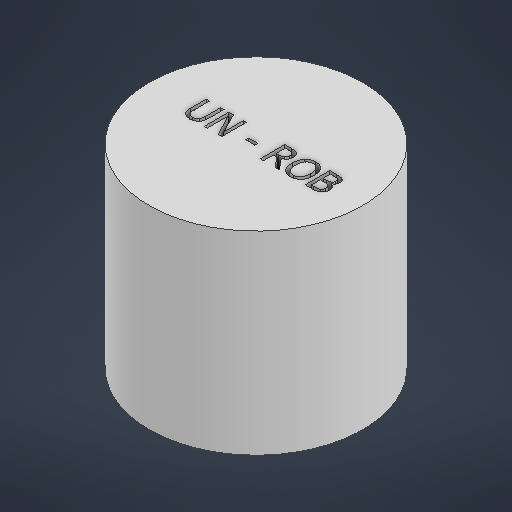
# Autodesk Inventor part: Tapa
Saved by Autodesk Inventor 2027.1 (Build 311270010, 270A)
## iProperties
Created: 2026-09-14
Part Number: Tapa
Material: Genérico
Document SubType Name: Modeling
Designer: felip
Density: 1 g/cm^3
Appearance: Valor por defecto
Author: felip
Autodesk Inventor part; units mm, degrees
ref_plane "YZ Plane" through (0, 0, 0) normal (1, 0, 0) x (0, 1, 0)
ref_plane "XZ Plane" through (0, 0, 0) normal (0, 1, 0) x (-1, 0, 0)
ref_plane "XY Plane" through (0, 0, 0) normal (0, 0, 1) x (1, 0, 0)
sketch "Boceto1" plane through (0, 0, 0) normal (0, 0, 1) x (1, 0, 0)
  line L0 (-8.75, 0) -> (0, 0)
  line L1 (-8.75, 0) -> (-8.75, 15)
  line L2 (-8.75, 15) -> (-11.5, 15)
  line L3 (-11.5, 15) -> (-11.5, 0)
  line L4 (-11.5, 0) -> (-13.75, 0)
  line L5 (-13.75, 0) -> (-13.75, 25)
  line L6 (0, 0) -> (0, 34.232) construction
  line L7 (-13.75, 25) -> (0, 25)
  line L8 (0, 0) -> (0, 25)
  dimension "d1" = 15
  dimension "d2" = 2.75
  dimension "d3" = 15
  dimension "d4" = 2.25
  dimension "d5" = 25
  dimension "d6" = 8.75
  constraints: 18 end point, 5 perpendicular, 3 point on line, 2 vertical, 1 collinear, 1 horizontal
  measures "d1" distance of L0.start L1.end
  measures "d2" distance of L1.end L2.end
  measures "d3" distance of L2.end L3.end
  measures "d4" distance of L3.end L4.end
  measures "d5" distance of L4.end L5.end
  measures "d6" distance of L0.start L0.end
revolve "Revolución1" add sketch "Boceto1" angle 360 about axis through (0, 0, 0) along (0, 1, 0)
sketch "Boceto2" plane through (0, 25, 0) normal (0, 1, 0) x (1, 0, 0)
  line L0 (-10.7148, 4.7718) -> (12.2093, 4.7718) construction
  line L1 (12.2093, 4.7718) -> (12.2093, -1.4527) construction
  line L2 (12.2093, -1.4527) -> (-10.7148, -1.4527) construction
  line L3 (-10.7148, -1.4527) -> (-10.7148, 4.7718) construction
  spline S0 degree 2 poles (-7.0539, -1.4527) (-7.3343, -1.4527) (-7.7511, -1.306) (-7.8978, -1.1594) knots 0 0 0 1 2 2 2
  spline S1 degree 2 poles (-7.8978, -1.1594) (-8.065, -0.9947) (-8.2014, -0.5316) (-8.2014, -0.1919) knots 0 0 0 1 2 2 2
  line L4 (-8.2014, -0.1919) -> (-8.2014, 1.7892)
  line L5 (-8.2014, 1.7892) -> (-7.7794, 1.7892)
  line L6 (-7.7794, 1.7892) -> (-7.7794, -0.1919)
  spline S2 degree 2 poles (-7.7794, -0.1919) (-7.7794, -0.4132) (-7.7228, -0.7117) (-7.6431, -0.8326) knots 0 0 0 1 2 2 2
  spline S3 degree 2 poles (-7.6431, -0.8326) (-7.5582, -0.9612) (-7.2649, -1.0925) (-7.0539, -1.0925) knots 0 0 0 1 2 2 2
  spline S4 degree 2 poles (-7.0539, -1.0925) (-6.8558, -1.0925) (-6.547, -0.9612) (-6.4621, -0.8326) knots 0 0 0 1 2 2 2
  spline S5 degree 2 poles (-6.4621, -0.8326) (-6.3823, -0.7117) (-6.3257, -0.4158) (-6.3257, -0.2022) knots 0 0 0 1 2 2 2
  line L7 (-6.3257, -0.2022) -> (-6.3257, 1.7892)
  line L8 (-6.3257, 1.7892) -> (-5.9038, 1.7892)
  line L9 (-5.9038, 1.7892) -> (-5.9038, -0.1919)
  spline S6 degree 2 poles (-5.9038, -0.1919) (-5.9038, -0.5238) (-6.0376, -0.9973) (-6.2074, -1.1594) knots 0 0 0 1 2 2 2
  spline S7 degree 2 poles (-6.2074, -1.1594) (-6.3592, -1.3086) (-6.7606, -1.4527) (-7.0539, -1.4527) knots 0 0 0 1 2 2 2
  line L10 (-3.0272, -1.3858) -> (-3.5007, -1.3858)
  line L11 (-3.5007, -1.3858) -> (-4.9055, 1.3518)
  line L12 (-4.9055, 1.3518) -> (-4.9055, -1.3858)
  line L13 (-4.9055, -1.3858) -> (-5.2991, -1.3858)
  line L14 (-5.2991, -1.3858) -> (-5.2991, 1.7892)
  line L15 (-5.2991, 1.7892) -> (-4.6996, 1.7892)
  line L16 (-4.6996, 1.7892) -> (-3.4209, -0.7245)
  line L17 (-3.4209, -0.7245) -> (-3.4209, 1.7892)
  line L18 (-3.4209, 1.7892) -> (-3.0272, 1.7892)
  line L19 (-3.0272, 1.7892) -> (-3.0272, -1.3858)
  line L20 (0.0526, -0.1894) -> (-1.149, -0.1894)
  line L21 (-1.149, -0.1894) -> (-1.149, 0.1966)
  line L22 (-1.149, 0.1966) -> (0.0526, 0.1966)
  line L23 (0.0526, 0.1966) -> (0.0526, -0.1894)
  line L24 (4.3854, -1.3858) -> (3.8373, -1.3858)
  line L25 (3.8373, -1.3858) -> (2.8339, -0.1225)
  line L26 (2.8339, -0.1225) -> (2.3502, -0.1225)
  line L27 (2.3502, -0.1225) -> (2.3502, -1.3858)
  line L28 (2.3502, -1.3858) -> (1.9282, -1.3858)
  line L29 (1.9282, -1.3858) -> (1.9282, 1.7892)
  line L30 (1.9282, 1.7892) -> (2.7464, 1.7892)
  spline S8 degree 2 poles (2.7464, 1.7892) (3.0192, 1.7892) (3.3871, 1.7301) (3.5543, 1.622) knots 0 0 0 1 2 2 2
  spline S9 degree 2 poles (3.5543, 1.622) (3.7216, 1.5139) (3.9145, 1.1769) (3.9145, 0.9273) knots 0 0 0 1 2 2 2
  spline S10 degree 2 poles (3.9145, 0.9273) (3.9145, 0.58) (3.5595, 0.1091) (3.2559, -0.0041) knots 0 0 0 1 2 2 2
  line L31 (3.2559, -0.0041) -> (4.3854, -1.3858)
  spline S11 degree 2 poles (3.4746, 0.8938) (3.4746, 1.0328) (3.3768, 1.2463) (3.2739, 1.3158) knots 0 0 0 1 2 2 2
  spline S12 degree 2 poles (3.2739, 1.3158) (3.1838, 1.375) (2.9445, 1.4239) (2.7696, 1.4239) knots 0 0 0 1 2 2 2
  line L32 (2.7696, 1.4239) -> (2.3502, 1.4239)
  line L33 (2.3502, 1.4239) -> (2.3502, 0.23)
  line L34 (2.3502, 0.23) -> (2.7207, 0.23)
  spline S13 degree 2 poles (2.7207, 0.23) (2.9034, 0.23) (3.1941, 0.2944) (3.2945, 0.3947) knots 0 0 0 1 2 2 2
  spline S14 degree 2 poles (3.2945, 0.3947) (3.3871, 0.4822) (3.4746, 0.7292) (3.4746, 0.8938) knots 0 0 0 1 2 2 2
  spline S15 degree 2 poles (6.8837, 1.4264) (7.0638, 1.2155) (7.2645, 0.598) (7.2645, 0.2017) knots 0 0 0 1 2 2 2
  spline S16 degree 2 poles (7.2645, 0.2017) (7.2645, -0.1842) (7.069, -0.8094) (6.8837, -1.0204) knots 0 0 0 1 2 2 2
  spline S17 degree 2 poles (6.8837, -1.0204) (6.6882, -1.2417) (6.171, -1.4527) (5.8597, -1.4527) knots 0 0 0 1 2 2 2
  spline S18 degree 2 poles (5.8597, -1.4527) (5.5381, -1.4527) (5.0235, -1.234) (4.8356, -1.0204) knots 0 0 0 1 2 2 2
  spline S19 degree 2 poles (4.8356, -1.0204) (4.653, -0.8094) (4.4574, -0.1894) (4.4574, 0.2017) knots 0 0 0 1 2 2 2
  spline S20 degree 2 poles (4.4574, 0.2017) (4.4574, 0.6005) (4.6555, 1.2077) (4.8382, 1.4264) knots 0 0 0 1 2 2 2
  spline S21 degree 2 poles (4.8382, 1.4264) (5.0235, 1.6374) (5.5406, 1.8561) (5.8597, 1.8561) knots 0 0 0 1 2 2 2
  spline S22 degree 2 poles (5.8597, 1.8561) (6.1839, 1.8561) (6.7036, 1.6297) (6.8837, 1.4264) knots 0 0 0 1 2 2 2
  spline S23 degree 2 poles (6.8245, 0.2017) (6.8245, 0.5156) (6.6882, 1.0019) (6.5647, 1.1614) knots 0 0 0 1 2 2 2
  spline S24 degree 2 poles (6.5647, 1.1614) (6.4386, 1.3261) (6.0835, 1.4908) (5.8622, 1.4908) knots 0 0 0 1 2 2 2
  spline S25 degree 2 poles (5.8622, 1.4908) (5.6333, 1.4908) (5.2885, 1.3312) (5.1573, 1.1614) knots 0 0 0 1 2 2 2
  spline S26 degree 2 poles (5.1573, 1.1614) (5.0312, 0.9993) (4.8974, 0.5105) (4.8974, 0.2017) knots 0 0 0 1 2 2 2
  spline S27 degree 2 poles (4.8974, 0.2017) (4.8974, -0.4235) (5.4223, -1.0873) (5.8622, -1.0873) knots 0 0 0 1 2 2 2
  spline S28 degree 2 poles (5.8622, -1.0873) (6.3022, -1.0873) (6.8245, -0.4235) (6.8245, 0.2017) knots 0 0 0 1 2 2 2
  spline S29 degree 2 poles (9.8812, -0.4106) (9.8812, -0.6473) (9.7011, -1.0101) (9.5518, -1.1285) knots 0 0 0 1 2 2 2
  spline S30 degree 2 poles (9.5518, -1.1285) (9.3717, -1.2674) (8.9626, -1.3858) (8.6384, -1.3858) knots 0 0 0 1 2 2 2
  line L35 (8.6384, -1.3858) -> (7.7276, -1.3858)
  line L36 (7.7276, -1.3858) -> (7.7276, 1.7892)
  line L37 (7.7276, 1.7892) -> (8.569, 1.7892)
  spline S31 degree 2 poles (8.569, 1.7892) (8.9086, 1.7892) (9.2482, 1.7455) (9.4026, 1.6606) knots 0 0 0 1 2 2 2
  spline S32 degree 2 poles (9.4026, 1.6606) (9.575, 1.5705) (9.7319, 1.2746) (9.7319, 1.074) knots 0 0 0 1 2 2 2
  spline S33 degree 2 poles (9.7319, 1.074) (9.7319, 0.8501) (9.4952, 0.495) (9.2868, 0.3947) knots 0 0 0 1 2 2 2
  line L38 (9.2868, 0.3947) -> (9.2868, 0.3793)
  spline S34 degree 2 poles (9.2868, 0.3793) (9.5698, 0.3021) (9.8812, -0.107) (9.8812, -0.4106) knots 0 0 0 1 2 2 2
  spline S35 degree 2 poles (9.4412, -0.4286) (9.4412, -0.2485) (9.3383, -0.017) (9.1839, 0.0654) knots 0 0 0 1 2 2 2
  spline S36 degree 2 poles (9.1839, 0.0654) (9.0836, 0.1168) (8.8468, 0.1477) (8.6282, 0.1477) knots 0 0 0 1 2 2 2
  line L39 (8.6282, 0.1477) -> (8.1496, 0.1477)
  line L40 (8.1496, 0.1477) -> (8.1496, -1.0256)
  line L41 (8.1496, -1.0256) -> (8.4918, -1.0256)
  spline S37 degree 2 poles (8.4918, -1.0256) (8.7697, -1.0256) (9.0887, -0.9741) (9.2122, -0.8918) knots 0 0 0 1 2 2 2
  spline S38 degree 2 poles (9.2122, -0.8918) (9.3306, -0.8069) (9.4412, -0.5959) (9.4412, -0.4286) knots 0 0 0 1 2 2 2
  spline S39 degree 2 poles (9.292, 1.0148) (9.292, 1.128) (9.2148, 1.2978) (9.1299, 1.3467) knots 0 0 0 1 2 2 2
  spline S40 degree 2 poles (9.1299, 1.3467) (9.027, 1.4033) (8.7774, 1.429) (8.5535, 1.429) knots 0 0 0 1 2 2 2
  line L42 (8.5535, 1.429) -> (8.1496, 1.429)
  line L43 (8.1496, 1.429) -> (8.1496, 0.5002)
  line L44 (8.1496, 0.5002) -> (8.6282, 0.5002)
  spline S41 degree 2 poles (8.6282, 0.5002) (8.8263, 0.5002) (9.0141, 0.5414) (9.1144, 0.6057) knots 0 0 0 1 2 2 2
  spline S42 degree 2 poles (9.1144, 0.6057) (9.2122, 0.6674) (9.292, 0.8655) (9.292, 1.0148) knots 0 0 0 1 2 2 2
  point P0 (0, 0)
  constraints: 2 other
emboss "Repujado1" sketch "Boceto2" operation cut depth 2 direction (0, -1, 0)
